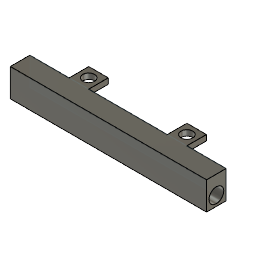
Accent light bar (Autodesk Fusion 360 design; units mm, degrees)
Autodesk Fusion 360 part; units mm, degrees
sketch "Sketch1" plane through (0, 0, 0) normal (0, 0, 1) x (1, 0, 0)
  line L0 (0, 0) -> (70, 0)
  line L1 (70, 0) -> (70, 7)
  line L2 (70, 7) -> (0, 7)
  line L3 (0, 7) -> (0, 0)
  dimension "d1" = 70
  dimension "d2" = 7
  constraint horizontal L0
  constraint vertical L1
  constraint horizontal L2
  constraint vertical L3
  constraint coincident L0.start L3.end
  measures "d1" distance of L0.start L0.end
  measures "d2" distance of L0.start L2.end
extrude "Extrude1" add sketch "Sketch1" along normal blind 7
sketch "Sketch2" plane through (70, 0, 0) normal (1, 0, 0) x (0, 1, 0)
  line L0 (0, 0) -> (7, 0)
  line L1 (7, 0) -> (7, 7)
  line L2 (7, 7) -> (0, 7)
  line L3 (0, 7) -> (0, 0)
  circle A0 centre (3.5, 3.5) radius 2.63
  dimension "d5" = 5.26
  measures "d5" diameter of A0
extrude "Extrude2" cut sketch "Sketch2" against normal blind 190 contours A0
extrude "Extrude3" add 1 faces at (23.3333, 4.6667, 7) along direction (0, 0, 1) blind 3
sketch "Sketch3" plane through (0, 7, 0) normal (0, 1, 0) x (-1, 0, 0)
  line L0 (-70, 0) -> (0, 0)
  line L1 (0, 0) -> (0, 10)
  line L2 (0, 10) -> (-70, 10)
  line L3 (-70, 10) -> (-70, 0)
sketch "Sketch4" plane through (0, 7, 0) normal (0, 1, 0) x (-1, 0, 0)
  line L0 (-49, 10) -> (-56, 10)
  line L1 (-56, 10) -> (-56, 8)
  line L2 (-56, 8) -> (-49, 8)
  line L3 (-49, 8) -> (-49, 10)
  line L4 (-21, 10) -> (-14, 10)
  line L5 (-14, 10) -> (-14, 8)
  line L6 (-14, 8) -> (-21, 8)
  line L7 (-21, 8) -> (-21, 10)
  constraint horizontal L0
  constraint vertical L1
  constraint horizontal L2
  constraint vertical L3
  constraint horizontal L4
  constraint vertical L5
  constraint horizontal L6
  constraint vertical L7
extrude "Extrude4" add sketch "Sketch4" along normal blind 7
sketch "Sketch5" plane through (0, 0, 10) normal (0, 0, 1) x (-1, 0, 0)
  line L0 (0, -7) -> (0, 0)
  line L1 (0, 0) -> (-70, 0)
  line L2 (-70, 0) -> (-70, -7)
  line L3 (-70, -7) -> (-56, -7)
  line L4 (-56, -7) -> (-56, -14)
  line L5 (-56, -14) -> (-49, -14)
  line L6 (-49, -14) -> (-49, -7)
  line L7 (-49, -7) -> (-21, -7)
  line L8 (-21, -7) -> (-21, -14)
  line L9 (-21, -14) -> (-14, -14)
  line L10 (-14, -14) -> (-14, -7)
  line L11 (-14, -7) -> (0, -7)
  circle A0 centre (-17.5, -10.5) radius 2.1
  circle A1 centre (-52.5, -10.5) radius 2.1
  dimension "d19" = 4.2
  dimension "d20" = 4.2
  measures "d19" diameter of A0
  measures "d20" diameter of A1
extrude "Extrude5" cut sketch "Sketch5" against normal blind 43587 contours A0 | A1
